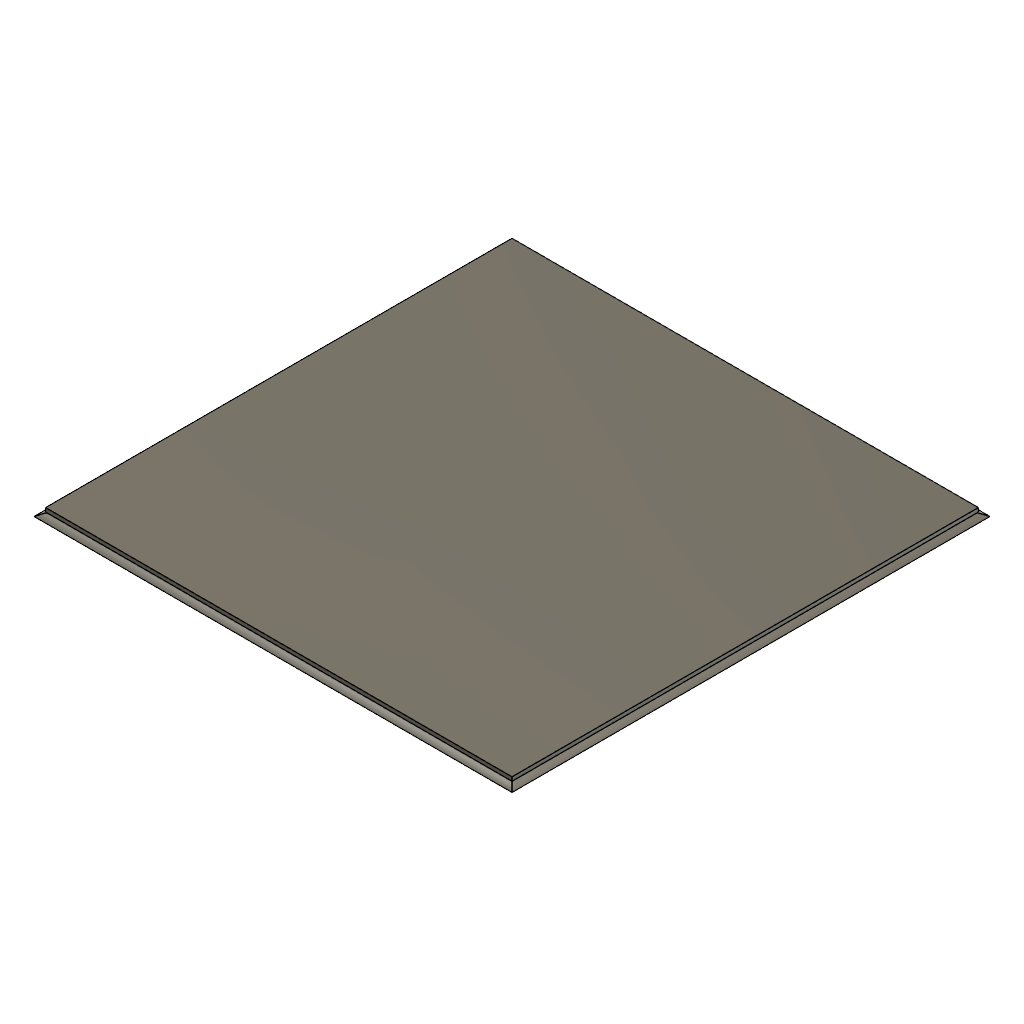
Board (Autodesk Fusion 360 design; units mm, degrees)
part number: 2026-10-15-21-07-23-463
part number: 2026-10-15-21-11-25-391
Autodesk Fusion 360 part; units mm, degrees
sketch "Sketch1" plane through (0, 0, 0) normal (0, 1, 0) x (1, 0, 0)
  line L0 (120, -120) -> (-120, -120)
  line L1 (-120, -120) -> (-120, 120)
  line L2 (-120, 120) -> (120, 120)
  line L3 (120, 120) -> (120, -120)
  line L4 (120, -120) -> (-120, 120) construction
  line L5 (-120, -120) -> (120, 120) construction
  dimension "d1" = 240
  dimension "d2" = 240
  constraint horizontal L0
  constraint perpendicular L0 L1
  constraint parallel L0 L2
  constraint parallel L1 L3
  constraint coincident L4 origin
  constraint coincident L5 origin
  measures "d1" distance of L1.end L2.end
  measures "d2" distance of L0.end L1.end
extrude "Extrude2" add sketch "Sketch1" along normal blind 2 makes body 1
sketch "Sketch2" plane through (0, 0, 0) normal (0, -1, 0) x (1, 0, 0)
  line L0 (-120, -120) -> (120, -120) construction
  line L1 (120, -120) -> (120, 120) construction
  line L2 (120, 120) -> (-120, 120) construction
  line L3 (-120, 120) -> (-120, -120) construction
  line L4 (-123, 123) -> (-123, -123)
  line L5 (-123, -123) -> (123, -123)
  line L6 (123, -123) -> (123, 123)
  line L7 (123, 123) -> (-123, 123)
  dimension "d5" = 3
extrude "Extrude2'" add sketch "Sketch2" along normal blind 2 makes body 2 in component "Component"
fillet "Fillet1" radius 10 4 edges at (0, 0, 123) (-123, 0, 0) (0, 0, -123) (123, 0, 0) on bodies 2 in component "Component"
sketch "Sketch3" plane through (0, -2, 0) normal (0, -1, 0) x (1, 0, 0)
  line L0 (123, 123) -> (-123, 123)
  line L1 (-123, 123) -> (-123, -123)
  line L2 (-123, -123) -> (123, -123)
  line L3 (123, -123) -> (123, 123)
  circle A0 centre (-108, 108) radius 3.15
  circle A1 centre (108, 108) radius 3.15
  circle A2 centre (-108, -108) radius 3.15
  circle A3 centre (-77.1429, 108) radius 3.15
  circle A4 centre (-46.2857, 108) radius 3.15
  circle A5 centre (-15.4286, 108) radius 3.15
  circle A6 centre (15.4286, 108) radius 3.15
  circle A7 centre (46.2857, 108) radius 3.15
  circle A8 centre (77.1429, 108) radius 3.15
  circle A9 centre (108, 108) radius 3.15
  circle A10 centre (-108, 77.1429) radius 3.15
  circle A11 centre (-77.1429, 77.1429) radius 3.15
  circle A12 centre (-46.2857, 77.1429) radius 3.15
  circle A13 centre (-15.4286, 77.1429) radius 3.15
  circle A14 centre (15.4286, 77.1429) radius 3.15
  circle A15 centre (46.2857, 77.1429) radius 3.15
  circle A16 centre (77.1429, 77.1429) radius 3.15
  circle A17 centre (108, 77.1429) radius 3.15
  circle A18 centre (-108, 46.2857) radius 3.15
  circle A19 centre (-77.1429, 46.2857) radius 3.15
  circle A20 centre (-46.2857, 46.2857) radius 3.15
  circle A21 centre (-15.4286, 46.2857) radius 3.15
  circle A22 centre (15.4286, 46.2857) radius 3.15
  circle A23 centre (46.2857, 46.2857) radius 3.15
  circle A24 centre (77.1429, 46.2857) radius 3.15
  circle A25 centre (108, 46.2857) radius 3.15
  circle A26 centre (-108, 15.4286) radius 3.15
  circle A27 centre (-77.1429, 15.4286) radius 3.15
  circle A28 centre (-46.2857, 15.4286) radius 3.15
  circle A29 centre (-15.4286, 15.4286) radius 3.15
  circle A30 centre (15.4286, 15.4286) radius 3.15
  circle A31 centre (46.2857, 15.4286) radius 3.15
  circle A32 centre (77.1429, 15.4286) radius 3.15
  circle A33 centre (108, 15.4286) radius 3.15
  circle A34 centre (-108, -15.4286) radius 3.15
  circle A35 centre (-77.1429, -15.4286) radius 3.15
  circle A36 centre (-46.2857, -15.4286) radius 3.15
  circle A37 centre (-15.4286, -15.4286) radius 3.15
  circle A38 centre (15.4286, -15.4286) radius 3.15
  circle A39 centre (46.2857, -15.4286) radius 3.15
  circle A40 centre (77.1429, -15.4286) radius 3.15
  circle A41 centre (108, -15.4286) radius 3.15
  circle A42 centre (-108, -46.2857) radius 3.15
  circle A43 centre (-77.1429, -46.2857) radius 3.15
  circle A44 centre (-46.2857, -46.2857) radius 3.15
  circle A45 centre (-15.4286, -46.2857) radius 3.15
  circle A46 centre (15.4286, -46.2857) radius 3.15
  circle A47 centre (46.2857, -46.2857) radius 3.15
  circle A48 centre (77.1429, -46.2857) radius 3.15
  circle A49 centre (108, -46.2857) radius 3.15
  circle A50 centre (-108, -77.1429) radius 3.15
  circle A51 centre (-77.1429, -77.1429) radius 3.15
  circle A52 centre (-46.2857, -77.1429) radius 3.15
  circle A53 centre (-15.4286, -77.1429) radius 3.15
  circle A54 centre (15.4286, -77.1429) radius 3.15
  circle A55 centre (46.2857, -77.1429) radius 3.15
  circle A56 centre (77.1429, -77.1429) radius 3.15
  circle A57 centre (108, -77.1429) radius 3.15
  circle A58 centre (-108, -108) radius 3.15
  circle A59 centre (-77.1429, -108) radius 3.15
  circle A60 centre (-46.2857, -108) radius 3.15
  circle A61 centre (-15.4286, -108) radius 3.15
  circle A62 centre (15.4286, -108) radius 3.15
  circle A63 centre (46.2857, -108) radius 3.15
  circle A64 centre (77.1429, -108) radius 3.15
  circle A65 centre (108, -108) radius 3.15
  dimension "d10" = 6.3
  dimension "d13" = 15
  dimension "d14" = 15
  dimension "d15" = 6.3
  dimension "d16" = 15
  dimension "d17" = 15
  dimension "d18" = 6.3
  dimension "d19" = 15
  dimension "d20" = 15
  dimension "d23" = 216
  dimension "d24" = -216
  measures "d10" diameter of A0
  measures "d13" distance of L1 A0.centre
  measures "d14" distance of L0 A0.centre
  measures "d15" diameter of A1
  measures "d16" distance of L3 A1.centre
  measures "d17" distance of L0 A1.centre
  measures "d18" diameter of A2
  measures "d19" distance of L2 A2.centre
  measures "d20" distance of L1 A2.centre
extrude "Extrude3" cut sketch "Sketch3" against normal blind 2.2 contours A0 bodies 2 in component "Component"
extrude "Extrude4" cut sketch "Sketch3" against normal blind 2.2 contours A0 | A1 A9 | A3 | A4 | A5 | A6 | A7 | A8 bodies 2 in component "Component"
extrude "Extrude5" cut sketch "Sketch3" against normal blind 2.2 contours A10 | A11 | A12 | A13 | A14 | A15 | A16 | A17 bodies 2 in component "Component"
extrude "Extrude6" cut sketch "Sketch3" against normal blind 2.2 contours A18 | A19 | A20 | A21 | A22 | A23 | A24 | A25 bodies 2 in component "Component"
extrude "Extrude7" cut sketch "Sketch3" against normal blind 2.2 contours A26 | A27 | A28 | A29 | A30 | A31 | A32 | A33 bodies 2 in component "Component"
extrude "Extrude8" cut sketch "Sketch3" against normal blind 2.2 contours A34 | A35 | A36 | A37 | A38 | A39 | A40 | A41 bodies 2 in component "Component"
extrude "Extrude9" cut sketch "Sketch3" against normal blind 2.2 contours A42 | A43 | A44 | A45 | A46 | A47 | A48 | A49 bodies 2 in component "Component"
extrude "Extrude10" cut sketch "Sketch3" against normal blind 2.2 contours A50 | A51 | A52 | A53 | A54 | A55 | A56 | A57 bodies 2 in component "Component"
extrude "Extrude3'" cut sketch "Sketch3" against normal blind 2.2 contours A2 A58 | A59 | A60 | A61 | A62 | A63 | A64 | A65 bodies 1
extrude "Extrude12" cut sketch "Sketch3" against normal blind 2.2 contours A2 A58 | A59 | A60 | A61 | A62 | A63 | A64 | A65 bodies 2 in component "Component"
extrude "Extrude11" [suppressed] in component "Component"
component "Component" placed x (1, 0, 0) y (0, 1, 0) z (0, 0, 1) at (0, 0, 0)
